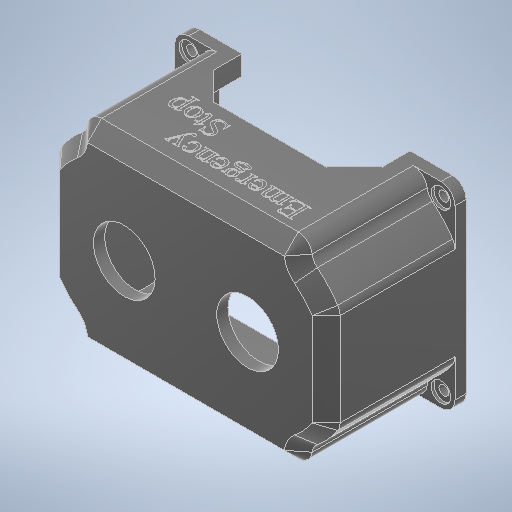
# Autodesk Inventor part: 3D_Estop-fix
Saved by Autodesk Inventor 2025.3 (Build 293356030, 356C)
## iProperties
Created: 2025-09-04
Part Number: 3D_Estop-fix
Material: 一般
Document SubType Name: Modeling
Designer: ibuki_ono
Density: 1 g/cm^3
Appearance: 滑らか - 黒
Author: ibuki_ono
## iProperties of the stored document 3D_Estop-fix_3D プリント.ipt
Created: 2025-09-05
Part Number: 3D_Estop-fix_3D プリント
Material: 一般
Document SubType Name: Modeling
Designer: ibuki_ono
Density: 1 g/cm^3
Appearance: 既定
Author: ibuki_ono
Autodesk Inventor part; units mm, degrees
ref_plane "YZ Plane" through (0, 0, 0) normal (1, 0, 0) x (0, 1, 0)
ref_plane "XZ Plane" through (0, 0, 0) normal (0, 1, 0) x (-1, 0, 0)
ref_plane "XY Plane" through (0, 0, 0) normal (0, 0, 1) x (1, 0, 0)
sketch "スケッチ1" plane through (0, 0, 0) normal (0, 0, 1) x (1, 0, 0)
  line L0 (-50, -35) -> (50, -35)
  line L1 (50, -35) -> (50, 35)
  line L2 (50, 35) -> (-50, 35)
  line L3 (-50, 35) -> (-50, -35)
  line L4 (-50, -35) -> (50, 35) construction
  line L5 (50, -35) -> (-50, 35) construction
  point P0 (0, 0)
  dimension "d0" = 100
  dimension "d1" = 70
  constraints: 12 end point, 2 midpoint, 2 parallel, 1 horizontal, 1 perpendicular
  measures "d0" distance of L2.end L1.end
  measures "d1" distance of L1.end L0.end
extrude "押し出し1" add sketch "スケッチ1" along normal blind 50
sketch "スケッチ2" plane through (0, 0, 50) normal (0, 0, 1) x (1, 0, 0)
  circle A0 centre (-22, 0) radius 11
  point P0 (0, 0)
  dimension "d4" = 22
  dimension "d5" = 22
  constraints: 1 centre point, 1 horizontal alignment
  measures "d4" diameter of A0
  measures "d5" distance of point (0, 0) A0.centre
extrude "押し出し2" cut sketch "スケッチ2" against normal through all
sketch "スケッチ3" plane through (0, 0, 0) normal (0, 0, -1) x (-1, 0, 0)
  line L0 (-38, 28) -> (38, 28)
  line L1 (38, 28) -> (38, -28)
  line L2 (38, -28) -> (-38, -28)
  line L3 (-38, -28) -> (-38, 28)
  line L4 (-38, 28) -> (38, -28) construction
  line L5 (38, 28) -> (-38, -28) construction
  circle A0 centre (22, 0) radius 11 projected
  point P0 (0, 0)
  dimension "d8" = 16
  dimension "d9" = 56
  constraints: 12 end point, 2 midpoint, 2 parallel, 1 horizontal, 1 perpendicular
  measures "d8" distance from line of L1 A0.centre
  measures "d9" distance of L0.end L1.end
extrude "押し出し3" cut sketch "スケッチ3" against normal blind 46
sketch "スケッチ4" plane through (0, 0, 50) normal (0, 0, 1) x (1, 0, 0)
  circle A0 centre (22, 0) radius 11
  point P0 (0, 0)
  dimension "d12" = 22
  dimension "d13" = 22
  constraints: 1 centre point, 1 horizontal alignment
  measures "d12" distance of point (0, 0) A0.centre
  measures "d13" diameter of A0
extrude "押し出し4" cut sketch "スケッチ4" against normal through all
sketch "スケッチ5" plane through (0, 0, 50) normal (0, 0, 1) x (1, 0, 0)
  circle A0 centre (-22, 0) radius 11 projected
  line L0 (50, -35) -> (50, 35) projected
  line L1 (50, 35) -> (-50, 35) projected
  line L2 (-50, 35) -> (-50, -35) projected
  line L3 (-50, -35) -> (50, -35) projected
  circle A1 centre (-20, 0) radius 35
  line L4 (-40, 35) -> (-40, -35)
  point P0 (0, 0)
  point P1 (-40, 28.7228)
  point P2 (-50, 18.0278)
  point P3 (-40, -28.7228)
  point P4 (-50, -18.0278)
  dimension "d16" = 70
  dimension "d17" = 10
  constraints: 2 end point, 2 point on line, 1 centre point, 1 perpendicular
  measures "d16" diameter of A1
  measures "d17" distance between parallel lines of L2 L4
extrude "押し出し5" cut sketch "スケッチ5" against normal blind 46 contours L3 L2 A1 L4 | L4 A1 L2 L1
sketch "スケッチ6" plane through (0, 0, 4) normal (0, 0, 1) x (1, 0, 0)
  line L0 (-50, 35) -> (-40, 35) projected
  line L1 (-40, -35) -> (-50, -35) projected
  line L2 (-45, 35) -> (-45, -35) construction
  point P0 (0, 0)
  point P1 (-45, 30)
  point P2 (-45, -30)
  dimension "d20" = 5
  dimension "d21" = 5
  constraints: 2 end point, 2 midpoint, 2 point on line
  measures "d20" distance from line of L0 point (-45, 30)
  measures "d21" distance from line of L1 point (-45, -30)
hole "穴1" at (-45, 30, 4) at (-45, -30, 4) direction (0, 0, -1) diameter 3.5 end through all counterbore diameter 7 counterbore depth 1
mirror "ミラー1" about plane through (0, 0, 0) normal (1, 0, 0) of "押し出し5", "穴1"
fillet "フィレット1" radius 5 16 edges at (-50, -35, 2) (-50, -18.0278, 27) (-40, -35, 27) (-40, -28.7228, 27) (40, -35, 27) (50, -35, 2) (40, -28.7228, 27) (50, -18.0278, 27) (50, 18.0278, 27) (40, 28.7228, 27) (40, 35, 27) (50, 35, 2) (-40, 35, 27) (-40, 28.7228, 27) (-50, 18.0278, 27) (-50, 35, 2)
chamfer "面取り1" distance 5 angle 45 20 edges at (0, 35, 50) (-38.3872, 33.7458, 50) (-40.6344, 28.7874, 50) (-45.8305, 23.6175, 50) (-49.7871, 18.0265, 50) (-50, 0, 50) (-49.7871, -18.0265, 50) (-45.8305, -23.6175, 50) (-40.6344, -28.7874, 50) (-38.3872, -33.7458, 50) (0, -35, 50) (38.3872, -33.7458, 50) (40.6344, -28.7874, 50) (45.8305, -23.6175, 50) (49.7871, -18.0265, 50) (50, 0, 50) (49.7871, 18.0265, 50) (45.8305, 23.6175, 50) (40.6344, 28.7874, 50) (38.3872, 33.7458, 50)
sketch "スケッチ7" plane through (-45, 35, 0) normal (0, 1, 0) x (1, 0, 0)
  line L0 (90, 0) -> (0, 0) projected
  line L1 (0, 0) -> (90, 0) projected
  line L2 (75, 0) -> (15, 0)
  line L3 (15, 0) -> (15, -20)
  line L4 (15, -20) -> (75, -20)
  line L5 (75, -20) -> (75, 0)
  point P0 (45, 0)
  point P1 (45, 0)
  point P2 (45, 0)
  point P3 (15, 0)
  dimension "d33" = 60
  dimension "d34" = 20
  constraints: 8 end point, 4 midpoint, 2 parallel, 1 horizontal, 1 perpendicular, 1 point on line
  measures "d33" distance of L4.end L3.end
  measures "d34" distance of L3.end L2.end
extrude "押し出し6" cut sketch "スケッチ7" against normal through all
chamfer "面取り2" distance 10 angle 45 4 edges at (30, 31.5, 20) (-30, 31.5, 20) (30, -31.5, 20) (-30, -31.5, 20)
sketch "スケッチ8" plane through (-45, 35, 4) normal (0, 1, 0) x (1, 0, 0)
  line L0 (75.4109, -38.3086) -> (10.7942, -38.3086) construction
  line L1 (10.7942, -38.3086) -> (10.7942, -18.6159) construction
  line L2 (10.7942, -18.6159) -> (75.4109, -18.6159) construction
  line L3 (75.4109, -18.6159) -> (75.4109, -38.3086) construction
  line L4 (73.2034, -37.9254) -> (73.2034, -35.1632)
  line L5 (73.2034, -35.1632) -> (71.665, -35.1632)
  spline S0 degree 2 poles (71.665, -35.1632) (71.0645, -35.1632) (70.8643, -35.3462) knots 0 0 0 1 1 1
  spline S1 degree 2 poles (70.8643, -35.3462) (70.5898, -35.5806) (70.5612, -36.1811) knots 0 0 0 1 1 1
  line L6 (70.5612, -36.1811) -> (70.3725, -36.1811)
  line L7 (70.3725, -36.1811) -> (70.3725, -33.7391)
  line L8 (70.3725, -33.7391) -> (70.5612, -33.7391)
  spline S2 degree 2 poles (70.5612, -33.7391) (70.6356, -34.2481) (70.7042, -34.3911) knots 0 0 0 1 1 1
  spline S3 degree 2 poles (70.7042, -34.3911) (70.8014, -34.5741) (71.2246, -34.78) (71.665, -34.78) knots 0 0 0 1 2 2 2
  line L9 (71.665, -34.78) -> (73.2034, -34.78)
  line L10 (73.2034, -34.78) -> (73.2034, -32.4752)
  spline S4 degree 2 poles (73.2034, -32.4752) (73.2034, -32.012) (73.1233, -31.8118) (72.9117, -31.6917) (72.6258, -31.6917) knots 0 0 0 1 2 3 3 3
  line L11 (72.6258, -31.6917) -> (71.4362, -31.6917)
  spline S5 degree 2 poles (71.4362, -31.6917) (70.8415, -31.6917) (70.3039, -31.8576) (70.058, -32.0978) knots 0 0 0 1 2 2 2
  spline S6 degree 2 poles (70.058, -32.0978) (69.7377, -32.4181) (69.4003, -33.0643) knots 0 0 0 1 1 1
  line L12 (69.4003, -33.0643) -> (69.1944, -33.0643)
  line L13 (69.1944, -33.0643) -> (69.8006, -31.3086)
  line L14 (69.8006, -31.3086) -> (75.1936, -31.3086)
  line L15 (75.1936, -31.3086) -> (75.1936, -31.4973)
  line L16 (75.1936, -31.4973) -> (74.9477, -31.4973)
  spline S7 degree 2 poles (74.9477, -31.4973) (74.696, -31.4973) (74.4787, -31.6174) knots 0 0 0 1 1 1
  spline S8 degree 2 poles (74.4787, -31.6174) (74.3129, -31.7032) (74.1928, -32.0349) (74.1928, -32.5496) knots 0 0 0 1 2 2 2
  line L17 (74.1928, -32.5496) -> (74.1928, -37.0904)
  spline S9 degree 2 poles (74.1928, -37.0904) (74.1928, -37.7596) (74.3243, -37.914) knots 0 0 0 1 1 1
  spline S10 degree 2 poles (74.3243, -37.914) (74.513, -38.1199) (74.9477, -38.1199) knots 0 0 0 1 1 1
  line L18 (74.9477, -38.1199) -> (75.1936, -38.1199)
  line L19 (75.1936, -38.1199) -> (75.1936, -38.3086)
  line L20 (75.1936, -38.3086) -> (69.7949, -38.3086)
  line L21 (69.7949, -38.3086) -> (69.7205, -36.7702)
  line L22 (69.7205, -36.7702) -> (69.9207, -36.7702)
  spline S11 degree 2 poles (69.9207, -36.7702) (70.0294, -37.3249) (70.2924, -37.7367) (70.5498, -37.8453) knots 0 0 0 1 2 2 2
  spline S12 degree 2 poles (70.5498, -37.8453) (70.7557, -37.9254) (71.2818, -37.9254) knots 0 0 0 1 1 1
  line L23 (71.2818, -37.9254) -> (73.2034, -37.9254)
  spline S13 degree 2 poles (67.2156, -35.1632) (66.7009, -35.6836) (66.6094, -35.7636) knots 0 0 0 1 1 1
  spline S14 degree 2 poles (66.6094, -35.7636) (66.3749, -35.9581) (65.8374, -36.1754) (65.5743, -36.1754) knots 0 0 0 1 2 2 2
  spline S15 degree 2 poles (65.5743, -36.1754) (65.1282, -36.1754) (64.4877, -35.655) (64.3848, -35.1632) knots 0 0 0 1 2 2 2
  spline S16 degree 2 poles (64.3848, -35.1632) (63.8529, -35.7865) (63.1209, -36.1754) (62.732, -36.1754) knots 0 0 0 1 2 2 2
  spline S17 degree 2 poles (62.732, -36.1754) (62.3545, -36.1754) (61.7769, -35.7865) (61.6053, -35.3519) knots 0 0 0 1 2 2 2
  spline S18 degree 2 poles (61.6053, -35.3519) (61.491, -35.0488) (61.491, -34.4083) knots 0 0 0 1 1 1
  line L24 (61.491, -34.4083) -> (61.491, -32.378)
  spline S19 degree 2 poles (61.491, -32.378) (61.491, -31.9377) (61.4223, -31.7718) knots 0 0 0 1 1 1
  spline S20 degree 2 poles (61.4223, -31.7718) (61.3709, -31.6574) (61.0906, -31.4973) (60.7761, -31.4973) knots 0 0 0 1 2 2 2
  line L25 (60.7761, -31.4973) -> (60.7761, -31.3086)
  line L26 (60.7761, -31.3086) -> (63.1151, -31.3086)
  line L27 (63.1151, -31.3086) -> (63.1151, -31.4973)
  line L28 (63.1151, -31.4973) -> (63.0179, -31.4973)
  spline S21 degree 2 poles (63.0179, -31.4973) (62.7091, -31.4973) (62.5375, -31.6174) knots 0 0 0 1 1 1
  spline S22 degree 2 poles (62.5375, -31.6174) (62.4232, -31.6975) (62.3717, -31.8805) knots 0 0 0 1 1 1
  spline S23 degree 2 poles (62.3717, -31.8805) (62.3488, -31.9663) (62.3488, -32.378) knots 0 0 0 1 1 1
  line L29 (62.3488, -32.378) -> (62.3488, -34.4083)
  spline S24 degree 2 poles (62.3488, -34.4083) (62.3488, -34.9859) (62.4861, -35.2203) knots 0 0 0 1 1 1
  spline S25 degree 2 poles (62.4861, -35.2203) (62.6862, -35.552) (63.1323, -35.552) knots 0 0 0 1 1 1
  spline S26 degree 2 poles (63.1323, -35.552) (63.4011, -35.552) (63.9558, -35.2775) (64.3447, -34.9058) knots 0 0 0 1 2 2 2
  line L30 (64.3447, -34.9058) -> (64.3562, -34.8486)
  line L31 (64.3562, -34.8486) -> (64.3447, -34.6313)
  line L32 (64.3447, -34.6313) -> (64.3447, -32.378)
  spline S27 degree 2 poles (64.3447, -32.378) (64.3447, -31.8919) (64.2361, -31.6574) (63.9387, -31.4973) (63.5784, -31.4973) knots 0 0 0 1 2 3 3 3
  line L33 (63.5784, -31.4973) -> (63.5784, -31.3086)
  line L34 (63.5784, -31.3086) -> (65.9689, -31.3086)
  line L35 (65.9689, -31.3086) -> (65.9689, -31.4973)
  spline S28 degree 2 poles (65.9689, -31.4973) (65.58, -31.4973) (65.2826, -31.6803) (65.2254, -31.869) knots 0 0 0 1 2 2 2
  spline S29 degree 2 poles (65.2254, -31.869) (65.2026, -31.9548) (65.2026, -32.378) knots 0 0 0 1 1 1
  line L36 (65.2026, -32.378) -> (65.2026, -34.4083)
  spline S30 degree 2 poles (65.2026, -34.4083) (65.2026, -34.9859) (65.3741, -35.2375) knots 0 0 0 1 1 1
  spline S31 degree 2 poles (65.3741, -35.2375) (65.5972, -35.5692) (66.0032, -35.5692) knots 0 0 0 1 1 1
  spline S32 degree 2 poles (66.0032, -35.5692) (66.2834, -35.5692) (66.558, -35.4205) knots 0 0 0 1 1 1
  spline S33 degree 2 poles (66.558, -35.4205) (66.9812, -35.1917) (67.2156, -34.9058) knots 0 0 0 1 1 1
  line L37 (67.2156, -34.9058) -> (67.2156, -32.378)
  spline S34 degree 2 poles (67.2156, -32.378) (67.2156, -31.9148) (67.0898, -31.6346) (66.8325, -31.4973) (66.4493, -31.4973) knots 0 0 0 1 2 3 3 3
  line L38 (66.4493, -31.4973) -> (66.4493, -31.3086)
  line L39 (66.4493, -31.3086) -> (68.7941, -31.3086)
  line L40 (68.7941, -31.3086) -> (68.7941, -31.4973)
  spline S35 degree 2 poles (68.7941, -31.4973) (68.4681, -31.4973) (68.2107, -31.6346) (68.0735, -31.9377) (68.0735, -32.378) knots 0 0 0 1 2 3 3 3
  line L41 (68.0735, -32.378) -> (68.0735, -34.1852)
  spline S36 degree 2 poles (68.0735, -34.1852) (68.0735, -34.963) (68.1192, -35.186) knots 0 0 0 1 1 1
  spline S37 degree 2 poles (68.1192, -35.186) (68.1535, -35.3576) (68.3137, -35.4891) (68.4452, -35.4891) knots 0 0 0 1 2 2 2
  spline S38 degree 2 poles (68.4452, -35.4891) (68.5882, -35.4891) (68.7883, -35.4091) knots 0 0 0 1 1 1
  line L42 (68.7883, -35.4091) -> (68.8684, -35.5978)
  line L43 (68.8684, -35.5978) -> (67.4387, -36.1754)
  line L44 (67.4387, -36.1754) -> (67.2156, -36.1754)
  line L45 (67.2156, -36.1754) -> (67.2156, -35.1632)
  spline S39 degree 2 poles (59.6037, -34.2538) (59.6094, -33.2016) (59.0947, -32.6068) knots 0 0 0 1 1 1
  spline S40 degree 2 poles (59.0947, -32.6068) (58.5743, -32.0063) (57.8766, -32.0063) knots 0 0 0 1 1 1
  spline S41 degree 2 poles (57.8766, -32.0063) (57.4133, -32.0063) (56.7271, -32.5153) (56.4926, -33.1386) knots 0 0 0 1 2 2 2
  line L46 (56.4926, -33.1386) -> (56.3325, -33.0357)
  spline S42 degree 2 poles (56.3325, -33.0357) (56.4411, -32.3266) (57.482, -31.1656) (58.2712, -31.1656) knots 0 0 0 1 2 2 2
  spline S43 degree 2 poles (58.2712, -31.1656) (59.1233, -31.1656) (60.3357, -32.4924) (60.3357, -33.6076) knots 0 0 0 1 2 2 2
  spline S44 degree 2 poles (60.3357, -33.6076) (60.3357, -34.82) (59.089, -36.1754) (58.1511, -36.1754) knots 0 0 0 1 2 2 2
  spline S45 degree 2 poles (58.1511, -36.1754) (57.3562, -36.1754) (56.3325, -35.1288) (56.3325, -34.2538) knots 0 0 0 1 2 2 2
  line L47 (56.3325, -34.2538) -> (59.6037, -34.2538)
  line L48 (59.6037, -34.5512) -> (57.4076, -34.5512)
  spline S46 degree 2 poles (57.4076, -34.5512) (57.4362, -35.003) (57.5163, -35.1917) knots 0 0 0 1 1 1
  spline S47 degree 2 poles (57.5163, -35.1917) (57.6478, -35.4777) (58.1568, -35.8094) (58.437, -35.8094) knots 0 0 0 1 2 2 2
  spline S48 degree 2 poles (58.437, -35.8094) (58.866, -35.8094) (59.5465, -35.146) (59.6037, -34.5512) knots 0 0 0 1 2 2 2
  line L49 (54.3137, -36.1754) -> (54.3137, -35.1117)
  spline S49 degree 2 poles (54.3137, -35.1117) (53.7189, -36.1754) (53.0955, -36.1754) knots 0 0 0 1 1 1
  spline S50 degree 2 poles (53.0955, -36.1754) (52.8153, -36.1754) (52.4436, -35.8323) (52.4436, -35.6035) knots 0 0 0 1 2 2 2
  spline S51 degree 2 poles (52.4436, -35.6035) (52.4436, -35.4034) (52.7124, -35.1231) (52.8954, -35.1231) knots 0 0 0 1 2 2 2
  spline S52 degree 2 poles (52.8954, -35.1231) (53.0784, -35.1231) (53.5245, -35.4777) (53.6331, -35.4777) knots 0 0 0 1 2 2 2
  spline S53 degree 2 poles (53.6331, -35.4777) (53.7246, -35.4777) (53.8333, -35.3748) knots 0 0 0 1 1 1
  spline S54 degree 2 poles (53.8333, -35.3748) (54.0678, -35.1632) (54.3137, -34.677) knots 0 0 0 1 1 1
  line L50 (54.3137, -34.677) -> (54.3137, -32.4123)
  spline S55 degree 2 poles (54.3137, -32.4123) (54.3137, -32.0177) (54.2165, -31.8176) knots 0 0 0 1 1 1
  spline S56 degree 2 poles (54.2165, -31.8176) (54.1478, -31.6803) (53.8104, -31.4973) (53.4901, -31.4973) knots 0 0 0 1 2 2 2
  line L51 (53.4901, -31.4973) -> (53.4901, -31.3086)
  line L52 (53.4901, -31.3086) -> (55.915, -31.3086)
  line L53 (55.915, -31.3086) -> (55.915, -31.4973)
  spline S57 degree 2 poles (55.915, -31.4973) (55.5547, -31.4973) (55.3774, -31.6117) knots 0 0 0 1 1 1
  spline S58 degree 2 poles (55.3774, -31.6117) (55.2516, -31.6917) (55.2001, -31.8748) knots 0 0 0 1 1 1
  spline S59 degree 2 poles (55.2001, -31.8748) (55.1715, -31.9663) (55.1715, -32.378) knots 0 0 0 1 1 1
  line L54 (55.1715, -32.378) -> (55.1715, -34.2024)
  spline S60 degree 2 poles (55.1715, -34.2024) (55.1715, -35.0259) (55.2401, -35.3404) (55.4174, -35.4891) (55.5547, -35.4891) knots 0 0 0 1 2 3 3 3
  spline S61 degree 2 poles (55.5547, -35.4891) (55.7148, -35.4891) (55.915, -35.4091) knots 0 0 0 1 1 1
  line L55 (55.915, -35.4091) -> (55.9665, -35.5978)
  line L56 (55.9665, -35.5978) -> (54.531, -36.1754)
  line L57 (54.531, -36.1754) -> (54.3137, -36.1754)
  spline S62 degree 2 poles (50.9166, -33.0357) (51.3513, -33.2473) (51.8145, -34.0022) (51.8145, -34.4654) knots 0 0 0 1 2 2 2
  spline S63 degree 2 poles (51.8145, -34.4654) (51.8145, -35.1632) (50.7565, -36.1754) (49.9272, -36.1754) knots 0 0 0 1 2 2 2
  spline S64 degree 2 poles (49.9272, -36.1754) (49.2524, -36.1754) (48.7548, -35.8437) knots 0 0 0 1 1 1
  line L58 (48.7548, -35.8437) -> (47.754, -35.8437)
  spline S65 degree 2 poles (47.754, -35.8437) (47.531, -35.8437) (47.4566, -35.8208) (47.4395, -35.7865) knots 0 0 0 1 2 2 2
  spline S66 degree 2 poles (47.4395, -35.7865) (47.4109, -35.7408) (47.4109, -35.6207) knots 0 0 0 1 1 1
  spline S67 degree 2 poles (47.4109, -35.6207) (47.4109, -35.4891) (47.4395, -35.4377) knots 0 0 0 1 1 1
  spline S68 degree 2 poles (47.4395, -35.4377) (47.4509, -35.4091) (47.531, -35.3805) (47.754, -35.3805) knots 0 0 0 1 2 2 2
  line L59 (47.754, -35.3805) -> (48.3717, -35.3805)
  spline S69 degree 2 poles (48.3717, -35.3805) (48.08, -35.0087) (48.08, -34.4311) knots 0 0 0 1 1 1
  spline S70 degree 2 poles (48.08, -34.4311) (48.08, -33.7677) (49.0923, -32.8298) (49.9444, -32.8298) knots 0 0 0 1 2 2 2
  spline S71 degree 2 poles (49.9444, -32.8298) (50.2932, -32.8298) (50.665, -32.9328) knots 0 0 0 1 1 1
  spline S72 degree 2 poles (50.665, -32.9328) (50.888, -32.7383) (51.0482, -32.4467) (51.0482, -32.3437) knots 0 0 0 1 2 2 2
  spline S73 degree 2 poles (51.0482, -32.3437) (51.0482, -32.2522) (50.8766, -32.0864) (50.6307, -32.052) knots 0 0 0 1 2 2 2
  spline S74 degree 2 poles (50.6307, -32.052) (50.4877, -32.0292) (49.9044, -32.0177) knots 0 0 0 1 1 1
  spline S75 degree 2 poles (49.9044, -32.0177) (48.8406, -31.9891) (48.5261, -31.9434) knots 0 0 0 1 1 1
  spline S76 degree 2 poles (48.5261, -31.9434) (48.0457, -31.8748) (47.4738, -31.2971) (47.4738, -30.8797) knots 0 0 0 1 2 2 2
  spline S77 degree 2 poles (47.4738, -30.8797) (47.4738, -30.2963) (48.0228, -29.7873) knots 0 0 0 1 1 1
  spline S78 degree 2 poles (48.0228, -29.7873) (48.8292, -29.0324) (50.1274, -29.0324) knots 0 0 0 1 1 1
  spline S79 degree 2 poles (50.1274, -29.0324) (51.1225, -29.0324) (51.8088, -29.4785) knots 0 0 0 1 1 1
  spline S80 degree 2 poles (51.8088, -29.4785) (52.1977, -29.7359) (52.1977, -30.0161) knots 0 0 0 1 1 1
  spline S81 degree 2 poles (52.1977, -30.0161) (52.1977, -30.1419) (52.1405, -30.262) knots 0 0 0 1 1 1
  spline S82 degree 2 poles (52.1405, -30.262) (52.0547, -30.4565) (51.7802, -30.7939) knots 0 0 0 1 1 1
  spline S83 degree 2 poles (51.7802, -30.7939) (51.7401, -30.8396) (51.254, -31.3486) knots 0 0 0 1 1 1
  spline S84 degree 2 poles (51.254, -31.3486) (51.5171, -31.5087) (51.7401, -31.7661) (51.7401, -31.9262) knots 0 0 0 1 2 2 2
  spline S85 degree 2 poles (51.7401, -31.9262) (51.7401, -32.1035) (51.4485, -32.5896) (50.9166, -33.0357) knots 0 0 0 1 2 2 2
  spline S86 degree 2 poles (50.9681, -31.3086) (51.214, -31.0455) (51.4599, -30.5937) (51.4599, -30.405) knots 0 0 0 1 2 2 2
  spline S87 degree 2 poles (51.4599, -30.405) (51.4599, -30.1591) (51.1625, -29.9761) knots 0 0 0 1 1 1
  spline S88 degree 2 poles (51.1625, -29.9761) (50.6421, -29.6558) (49.6642, -29.6558) knots 0 0 0 1 1 1
  spline S89 degree 2 poles (49.6642, -29.6558) (48.7377, -29.6558) (47.8513, -30.3078) (47.8513, -30.6738) knots 0 0 0 1 2 2 2
  spline S90 degree 2 poles (47.8513, -30.6738) (47.8513, -30.9426) (48.1143, -31.0569) knots 0 0 0 1 1 1
  spline S91 degree 2 poles (48.1143, -31.0569) (48.3831, -31.1656) (49.1781, -31.1885) knots 0 0 0 1 1 1
  spline S92 degree 2 poles (49.1781, -31.1885) (50.3447, -31.2171) (50.9681, -31.3086) knots 0 0 0 1 1 1
  spline S93 degree 2 poles (50.0187, -35.9295) (50.4019, -35.9295) (50.9166, -35.3233) (50.9166, -34.6942) knots 0 0 0 1 2 2 2
  spline S94 degree 2 poles (50.9166, -34.6942) (50.9166, -33.8764) (50.5678, -33.4303) knots 0 0 0 1 1 1
  spline S95 degree 2 poles (50.5678, -33.4303) (50.299, -33.0872) (49.8815, -33.0872) knots 0 0 0 1 1 1
  spline S96 degree 2 poles (49.8815, -33.0872) (49.4926, -33.0872) (48.9836, -33.6762) (48.9836, -34.3053) knots 0 0 0 1 2 2 2
  spline S97 degree 2 poles (48.9836, -34.3053) (48.9836, -35.1231) (49.3382, -35.5864) knots 0 0 0 1 1 1
  spline S98 degree 2 poles (49.3382, -35.5864) (49.6013, -35.9295) (50.0187, -35.9295) knots 0 0 0 1 1 1
  spline S99 degree 2 poles (46.0955, -34.2538) (46.1013, -33.2016) (45.5865, -32.6068) knots 0 0 0 1 1 1
  spline S100 degree 2 poles (45.5865, -32.6068) (45.0661, -32.0063) (44.3684, -32.0063) knots 0 0 0 1 1 1
  spline S101 degree 2 poles (44.3684, -32.0063) (43.9052, -32.0063) (43.2189, -32.5153) (42.9844, -33.1386) knots 0 0 0 1 2 2 2
  line L60 (42.9844, -33.1386) -> (42.8243, -33.0357)
  spline S102 degree 2 poles (42.8243, -33.0357) (42.933, -32.3266) (43.9738, -31.1656) (44.763, -31.1656) knots 0 0 0 1 2 2 2
  spline S103 degree 2 poles (44.763, -31.1656) (45.6151, -31.1656) (46.8276, -32.4924) (46.8276, -33.6076) knots 0 0 0 1 2 2 2
  spline S104 degree 2 poles (46.8276, -33.6076) (46.8276, -34.82) (45.5808, -36.1754) (44.6429, -36.1754) knots 0 0 0 1 2 2 2
  spline S105 degree 2 poles (44.6429, -36.1754) (43.848, -36.1754) (42.8243, -35.1288) (42.8243, -34.2538) knots 0 0 0 1 2 2 2
  line L61 (42.8243, -34.2538) -> (46.0955, -34.2538)
  line L62 (46.0955, -34.5512) -> (43.8995, -34.5512)
  spline S106 degree 2 poles (43.8995, -34.5512) (43.9281, -35.003) (44.0081, -35.1917) knots 0 0 0 1 1 1
  spline S107 degree 2 poles (44.0081, -35.1917) (44.1397, -35.4777) (44.6486, -35.8094) (44.9289, -35.8094) knots 0 0 0 1 2 2 2
  spline S108 degree 2 poles (44.9289, -35.8094) (45.3578, -35.8094) (46.0383, -35.146) (46.0955, -34.5512) knots 0 0 0 1 2 2 2
  spline S109 degree 2 poles (40.8112, -35.1746) (39.982, -36.1754) (39.2271, -36.1754) knots 0 0 0 1 1 1
  spline S110 degree 2 poles (39.2271, -36.1754) (38.8439, -36.1754) (38.2892, -35.7865) (38.1233, -35.3462) knots 0 0 0 1 2 2 2
  spline S111 degree 2 poles (38.1233, -35.3462) (38.0089, -35.0373) (38.0089, -34.3968) knots 0 0 0 1 1 1
  line L63 (38.0089, -34.3968) -> (38.0089, -32.378)
  spline S112 degree 2 poles (38.0089, -32.378) (38.0089, -31.9319) (37.9346, -31.7718) knots 0 0 0 1 1 1
  spline S113 degree 2 poles (37.9346, -31.7718) (37.8774, -31.6403) (37.6258, -31.4973) (37.2883, -31.4973) knots 0 0 0 1 2 2 2
  line L64 (37.2883, -31.4973) -> (37.2883, -31.3086)
  line L65 (37.2883, -31.3086) -> (39.6331, -31.3086)
  line L66 (39.6331, -31.3086) -> (39.6331, -31.4973)
  line L67 (39.6331, -31.4973) -> (39.5359, -31.4973)
  spline S114 degree 2 poles (39.5359, -31.4973) (39.2042, -31.4973) (38.9411, -31.6975) (38.8897, -31.8919) knots 0 0 0 1 2 2 2
  spline S115 degree 2 poles (38.8897, -31.8919) (38.8668, -31.972) (38.8668, -32.378) knots 0 0 0 1 1 1
  line L68 (38.8668, -32.378) -> (38.8668, -34.311)
  spline S116 degree 2 poles (38.8668, -34.311) (38.8668, -34.9573) (39.1985, -35.5406) (39.5931, -35.5406) knots 0 0 0 1 2 2 2
  spline S117 degree 2 poles (39.5931, -35.5406) (40.205, -35.5406) (40.8112, -34.8715) knots 0 0 0 1 1 1
  line L69 (40.8112, -34.8715) -> (40.8112, -32.378)
  spline S118 degree 2 poles (40.8112, -32.378) (40.8112, -31.8976) (40.754, -31.7833) knots 0 0 0 1 1 1
  spline S119 degree 2 poles (40.754, -31.7833) (40.6797, -31.6346) (40.4281, -31.4973) (40.0392, -31.4973) knots 0 0 0 1 2 2 2
  line L70 (40.0392, -31.4973) -> (40.0392, -31.3086)
  line L71 (40.0392, -31.3086) -> (42.3897, -31.3086)
  line L72 (42.3897, -31.3086) -> (42.3897, -31.4973)
  line L73 (42.3897, -31.4973) -> (42.2867, -31.4973)
  spline S120 degree 2 poles (42.2867, -31.4973) (41.9207, -31.4973) (41.6691, -31.8633) (41.6691, -32.378) knots 0 0 0 1 2 2 2
  line L74 (41.6691, -32.378) -> (41.6691, -34.1337)
  spline S121 degree 2 poles (41.6691, -34.1337) (41.6691, -34.9801) (41.7491, -35.3519) (41.9093, -35.4891) (42.0408, -35.4891) knots 0 0 0 1 2 3 3 3
  spline S122 degree 2 poles (42.0408, -35.4891) (42.1838, -35.4891) (42.3839, -35.4091) knots 0 0 0 1 1 1
  line L75 (42.3839, -35.4091) -> (42.464, -35.5978)
  line L76 (42.464, -35.5978) -> (41.0343, -36.1754)
  line L77 (41.0343, -36.1754) -> (40.8112, -36.1754)
  line L78 (40.8112, -36.1754) -> (40.8112, -35.1746)
  spline S123 degree 2 poles (32.8848, -33.1043) (33.0735, -32.1721) (34.1887, -31.1656) (34.8692, -31.1656) knots 0 0 0 1 2 2 2
  spline S124 degree 2 poles (34.8692, -31.1656) (35.6756, -31.1656) (36.8709, -32.5153) (36.8709, -33.6705) knots 0 0 0 1 2 2 2
  spline S125 degree 2 poles (36.8709, -33.6705) (36.8709, -34.78) (35.5441, -36.1754) (34.6119, -36.1754) knots 0 0 0 1 2 2 2
  spline S126 degree 2 poles (34.6119, -36.1754) (33.9142, -36.1754) (33.0163, -35.4377) (33.0163, -35.0431) knots 0 0 0 1 2 2 2
  spline S127 degree 2 poles (33.0163, -35.0431) (33.0163, -34.8429) (33.2679, -34.6027) (33.4967, -34.6027) knots 0 0 0 1 2 2 2
  spline S128 degree 2 poles (33.4967, -34.6027) (33.7998, -34.6027) (33.9542, -34.7971) knots 0 0 0 1 1 1
  spline S129 degree 2 poles (33.9542, -34.7971) (34.0457, -34.9058) (34.1029, -35.512) (34.2802, -35.6721) knots 0 0 0 1 2 2 2
  spline S130 degree 2 poles (34.2802, -35.6721) (34.4632, -35.8266) (34.7834, -35.8266) knots 0 0 0 1 1 1
  spline S131 degree 2 poles (34.7834, -35.8266) (35.3039, -35.8266) (35.6184, -35.4434) knots 0 0 0 1 1 1
  spline S132 degree 2 poles (35.6184, -35.4434) (36.0359, -34.9401) (36.0359, -34.1109) knots 0 0 0 1 1 1
  spline S133 degree 2 poles (36.0359, -34.1109) (36.0359, -33.2645) (35.2066, -31.972) (34.4975, -31.972) knots 0 0 0 1 2 2 2
  spline S134 degree 2 poles (34.4975, -31.972) (33.9885, -31.972) (33.5882, -32.3151) knots 0 0 0 1 1 1
  spline S135 degree 2 poles (33.5882, -32.3151) (33.3022, -32.5496) (33.0334, -33.1787) knots 0 0 0 1 1 1
  line L79 (33.0334, -33.1787) -> (32.8848, -33.1043)
  line L80 (32.4844, -36.0382) -> (30.2769, -36.0382)
  line L81 (30.2769, -36.0382) -> (30.2769, -35.8494)
  line L82 (30.2769, -35.8494) -> (30.3856, -35.8494)
  spline S136 degree 2 poles (30.3856, -35.8494) (30.6143, -35.8494) (30.8488, -35.6493) (30.8488, -35.5006) knots 0 0 0 1 2 2 2
  spline S137 degree 2 poles (30.8488, -35.5006) (30.8488, -35.2947) (30.6772, -34.9401) knots 0 0 0 1 1 1
  line L83 (30.6772, -34.9401) -> (29.522, -32.5496)
  line L84 (29.522, -32.5496) -> (28.4697, -35.1689)
  spline S138 degree 2 poles (28.4697, -35.1689) (28.3839, -35.3805) (28.3839, -35.5864) knots 0 0 0 1 1 1
  spline S139 degree 2 poles (28.3839, -35.5864) (28.3839, -35.6779) (28.4182, -35.7236) knots 0 0 0 1 1 1
  spline S140 degree 2 poles (28.4182, -35.7236) (28.4583, -35.7808) (28.6356, -35.8494) (28.8586, -35.8494) knots 0 0 0 1 2 2 2
  line L85 (28.8586, -35.8494) -> (28.8586, -36.0382)
  line L86 (28.8586, -36.0382) -> (27.3202, -36.0382)
  line L87 (27.3202, -36.0382) -> (27.3202, -35.8494)
  spline S141 degree 2 poles (27.3202, -35.8494) (27.5147, -35.8266) (27.7205, -35.7065) (27.8406, -35.5349) knots 0 0 0 1 2 2 2
  spline S142 degree 2 poles (27.8406, -35.5349) (27.8864, -35.4605) (28.0179, -35.1346) knots 0 0 0 1 1 1
  line L88 (28.0179, -35.1346) -> (29.9395, -30.4221)
  spline S143 degree 2 poles (29.9395, -30.4221) (30.2197, -29.7359) (31.1233, -29.0324) (31.5408, -29.0324) knots 0 0 0 1 2 2 2
  spline S144 degree 2 poles (31.5408, -29.0324) (31.8439, -29.0324) (32.2385, -29.3813) (32.2385, -29.61) knots 0 0 0 1 2 2 2
  spline S145 degree 2 poles (32.2385, -29.61) (32.2385, -29.8274) (31.9526, -30.0904) (31.7066, -30.0904) knots 0 0 0 1 2 2 2
  spline S146 degree 2 poles (31.7066, -30.0904) (31.5351, -30.0904) (31.2434, -29.9761) knots 0 0 0 1 1 1
  spline S147 degree 2 poles (31.2434, -29.9761) (31.0318, -29.9017) (30.9803, -29.9017) knots 0 0 0 1 1 1
  spline S148 degree 2 poles (30.9803, -29.9017) (30.8259, -29.9017) (30.4599, -30.222) (30.2769, -30.6795) knots 0 0 0 1 2 2 2
  line L89 (30.2769, -30.6795) -> (29.9452, -31.503)
  line L90 (29.9452, -31.503) -> (31.638, -35.0602)
  spline S149 degree 2 poles (31.638, -35.0602) (31.7181, -35.2203) (31.8897, -35.4605) knots 0 0 0 1 1 1
  spline S150 degree 2 poles (31.8897, -35.4605) (32.0155, -35.6435) (32.1013, -35.7065) knots 0 0 0 1 1 1
  spline S151 degree 2 poles (32.1013, -35.7065) (32.2214, -35.7865) (32.4844, -35.8494) knots 0 0 0 1 1 1
  line L91 (32.4844, -35.8494) -> (32.4844, -36.0382)
  line L92 (30.9174, -27.3972) -> (30.9174, -24.9781)
  line L93 (30.9174, -24.9781) -> (31.1062, -24.9781)
  spline S152 degree 2 poles (31.1062, -24.9781) (31.1977, -25.6758) (31.6838, -26.4993) (32.5702, -26.9854) (33.0506, -26.9854) knots 0 0 0 1 2 3 3 3
  spline S153 degree 2 poles (33.0506, -26.9854) (33.5882, -26.9854) (34.2916, -26.3278) (34.2916, -25.9103) knots 0 0 0 1 2 2 2
  spline S154 degree 2 poles (34.2916, -25.9103) (34.2916, -25.59) (34.0686, -25.327) knots 0 0 0 1 1 1
  spline S155 degree 2 poles (34.0686, -25.327) (33.7483, -24.9381) (32.5416, -24.2918) knots 0 0 0 1 1 1
  spline S156 degree 2 poles (32.5416, -24.2918) (31.5637, -23.7657) (30.8431, -23.2052) (30.4542, -22.4389) (30.4542, -22.0214) knots 0 0 0 1 2 3 3 3
  spline S157 degree 2 poles (30.4542, -22.0214) (30.4542, -21.2265) (31.6895, -20.077) (32.6617, -20.077) knots 0 0 0 1 2 2 2
  spline S158 degree 2 poles (32.6617, -20.077) (32.9648, -20.077) (33.2336, -20.1227) knots 0 0 0 1 1 1
  spline S159 degree 2 poles (33.2336, -20.1227) (33.3937, -20.1513) (34.4003, -20.4773) (34.5375, -20.4773) knots 0 0 0 1 2 2 2
  spline S160 degree 2 poles (34.5375, -20.4773) (34.6633, -20.4773) (34.8178, -20.3229) (34.8521, -20.077) knots 0 0 0 1 2 2 2
  line L94 (34.8521, -20.077) -> (35.0408, -20.077)
  line L95 (35.0408, -20.077) -> (35.0408, -22.4789)
  line L96 (35.0408, -22.4789) -> (34.8521, -22.4789)
  spline S161 degree 2 poles (34.8521, -22.4789) (34.7205, -21.724) (34.263, -20.9748) (33.3251, -20.4773) (32.7704, -20.4773) knots 0 0 0 1 2 3 3 3
  spline S162 degree 2 poles (32.7704, -20.4773) (32.1241, -20.4773) (31.3749, -21.1578) (31.3749, -21.6268) knots 0 0 0 1 2 2 2
  spline S163 degree 2 poles (31.3749, -21.6268) (31.3749, -21.8841) (31.6609, -22.4103) (31.9583, -22.639) knots 0 0 0 1 2 2 2
  spline S164 degree 2 poles (31.9583, -22.639) (32.1584, -22.7935) (33.9599, -23.8) (34.7205, -24.4005) (35.1151, -25.1211) (35.1151, -25.5557) knots 0 0 0 1 2 3 4 4 4
  spline S165 degree 2 poles (35.1151, -25.5557) (35.1151, -26.3106) (33.9542, -27.3972) (33.0563, -27.3972) knots 0 0 0 1 2 2 2
  spline S166 degree 2 poles (33.0563, -27.3972) (32.5016, -27.3972) (31.8725, -27.1227) knots 0 0 0 1 1 1
  spline S167 degree 2 poles (31.8725, -27.1227) (31.5808, -26.9969) (31.4607, -26.9969) knots 0 0 0 1 1 1
  spline S168 degree 2 poles (31.4607, -26.9969) (31.3292, -26.9969) (31.1576, -27.157) (31.1062, -27.3972) knots 0 0 0 1 2 2 2
  line L97 (31.1062, -27.3972) -> (30.9174, -27.3972)
  line L98 (28.1895, -26.5222) -> (28.1895, -24.9667)
  line L99 (28.1895, -24.9667) -> (27.0857, -24.9667)
  line L100 (27.0857, -24.9667) -> (27.0857, -24.6064)
  line L101 (27.0857, -24.6064) -> (28.1895, -24.6064)
  line L102 (28.1895, -24.6064) -> (28.1895, -21.5353)
  spline S169 degree 2 poles (28.1895, -21.5353) (28.1895, -21.0778) (27.9264, -20.7575) (27.7205, -20.7575) knots 0 0 0 1 2 2 2
  spline S170 degree 2 poles (27.7205, -20.7575) (27.549, -20.7575) (27.223, -20.9691) (27.1372, -21.175) knots 0 0 0 1 2 2 2
  line L103 (27.1372, -21.175) -> (26.937, -21.175)
  spline S171 degree 2 poles (26.937, -21.175) (27.12, -20.666) (27.7834, -20.157) (28.1323, -20.157) knots 0 0 0 1 2 2 2
  spline S172 degree 2 poles (28.1323, -20.157) (28.3725, -20.157) (28.83, -20.4201) (29.0473, -20.9119) (29.0473, -21.4209) knots 0 0 0 1 2 3 3 3
  line L104 (29.0473, -21.4209) -> (29.0473, -24.6064)
  line L105 (29.0473, -24.6064) -> (29.7965, -24.6064)
  line L106 (29.7965, -24.6064) -> (29.7965, -24.7779)
  spline S173 degree 2 poles (29.7965, -24.7779) (29.5106, -24.8923) (28.9158, -25.4299) (28.6813, -25.8016) knots 0 0 0 1 2 2 2
  spline S174 degree 2 poles (28.6813, -25.8016) (28.5612, -26.0018) (28.3496, -26.5222) knots 0 0 0 1 1 1
  line L107 (28.3496, -26.5222) -> (28.1895, -26.5222)
  spline S175 degree 2 poles (24.3178, -25.1039) (23.2426, -25.1039) (22.5964, -24.2861) knots 0 0 0 1 1 1
  spline S176 degree 2 poles (22.5964, -24.2861) (22.0416, -23.5941) (22.0416, -22.6905) knots 0 0 0 1 1 1
  spline S177 degree 2 poles (22.0416, -22.6905) (22.0416, -22.0557) (22.6535, -20.7518) (23.7173, -20.0941) (24.3749, -20.0941) knots 0 0 0 1 2 3 3 3
  spline S178 degree 2 poles (24.3749, -20.0941) (25.4444, -20.0941) (26.0735, -20.9462) knots 0 0 0 1 1 1
  spline S179 degree 2 poles (26.0735, -20.9462) (26.6053, -21.6611) (26.6053, -22.5533) knots 0 0 0 1 1 1
  spline S180 degree 2 poles (26.6053, -22.5533) (26.6053, -23.2052) (25.9591, -24.492) (24.9068, -25.1039) (24.3178, -25.1039) knots 0 0 0 1 2 3 3 3
  spline S181 degree 2 poles (24.4779, -24.7665) (24.7524, -24.7665) (25.3014, -24.4405) (25.6446, -23.6284) (25.6446, -22.9879) knots 0 0 0 1 2 3 3 3
  spline S182 degree 2 poles (25.6446, -22.9879) (25.6446, -21.9585) (24.8267, -20.4601) (24.1519, -20.4601) knots 0 0 0 1 2 2 2
  spline S183 degree 2 poles (24.1519, -20.4601) (23.6544, -20.4601) (23.0024, -21.2837) (23.0024, -22.2902) knots 0 0 0 1 2 2 2
  spline S184 degree 2 poles (23.0024, -22.2902) (23.0024, -23.5484) (23.5457, -24.2689) knots 0 0 0 1 1 1
  spline S185 degree 2 poles (23.5457, -24.2689) (23.9117, -24.7665) (24.4779, -24.7665) knots 0 0 0 1 1 1
  line L108 (21.6813, -24.4977) -> (20.223, -25.0868)
  line L109 (20.223, -25.0868) -> (20.0285, -25.0868)
  line L110 (20.0285, -25.0868) -> (20.0285, -23.9773)
  spline S186 degree 2 poles (20.0285, -23.9773) (19.6625, -24.6006) (18.9248, -25.1039) (18.5187, -25.1039) knots 0 0 0 1 2 2 2
  spline S187 degree 2 poles (18.5187, -25.1039) (17.8039, -25.1039) (17.3292, -24.5492) knots 0 0 0 1 1 1
  spline S188 degree 2 poles (17.3292, -24.5492) (16.7459, -23.8629) (16.7459, -22.7706) knots 0 0 0 1 1 1
  spline S189 degree 2 poles (16.7459, -22.7706) (16.7459, -21.5467) (17.4493, -20.7518) knots 0 0 0 1 1 1
  spline S190 degree 2 poles (17.4493, -20.7518) (18.0269, -20.0941) (18.9019, -20.0941) knots 0 0 0 1 1 1
  spline S191 degree 2 poles (18.9019, -20.0941) (19.2851, -20.0941) (19.5653, -20.2028) knots 0 0 0 1 1 1
  spline S192 degree 2 poles (19.5653, -20.2028) (19.7712, -20.2771) (20.0285, -20.5116) knots 0 0 0 1 1 1
  line L111 (20.0285, -20.5116) -> (20.0285, -19.0704)
  spline S193 degree 2 poles (20.0285, -19.0704) (20.0285, -18.5843) (19.9084, -18.3212) (19.6168, -18.1668) (19.2279, -18.1668) knots 0 0 0 1 2 3 3 3
  line L112 (19.2279, -18.1668) -> (19.2279, -17.9781)
  line L113 (19.2279, -17.9781) -> (21.7099, -17.9781)
  line L114 (21.7099, -17.9781) -> (21.7099, -18.1668)
  line L115 (21.7099, -18.1668) -> (21.5784, -18.1668)
  spline S194 degree 2 poles (21.5784, -18.1668) (21.2982, -18.1611) (21.0923, -18.2755) knots 0 0 0 1 1 1
  spline S195 degree 2 poles (21.0923, -18.2755) (20.995, -18.3327) (20.8864, -18.5843) (20.8864, -19.1047) knots 0 0 0 1 2 2 2
  line L116 (20.8864, -19.1047) -> (20.8864, -23.5712)
  spline S196 degree 2 poles (20.8864, -23.5712) (20.8864, -24.0345) (20.9665, -24.2804) (21.1495, -24.4062) (21.3039, -24.4062) knots 0 0 0 1 2 3 3 3
  spline S197 degree 2 poles (21.3039, -24.4062) (21.4297, -24.4062) (21.6184, -24.3319) knots 0 0 0 1 1 1
  line L117 (21.6184, -24.3319) -> (21.6813, -24.4977)
  line L118 (20.0285, -23.6742) -> (20.0285, -21.907)
  spline S198 degree 2 poles (20.0285, -21.907) (20.0285, -21.3351) (19.9828, -21.1578) knots 0 0 0 1 1 1
  spline S199 degree 2 poles (19.9828, -21.1578) (19.9084, -20.8547) (19.348, -20.4029) (18.9191, -20.4029) knots 0 0 0 1 2 2 2
  spline S200 degree 2 poles (18.9191, -20.4029) (18.4044, -20.4029) (18.0841, -20.8033) knots 0 0 0 1 1 1
  spline S201 degree 2 poles (18.0841, -20.8033) (17.6666, -21.3294) (17.6666, -22.2845) knots 0 0 0 1 1 1
  spline S202 degree 2 poles (17.6666, -22.2845) (17.6666, -23.3711) (18.1413, -23.9544) knots 0 0 0 1 1 1
  spline S203 degree 2 poles (18.1413, -23.9544) (18.473, -24.3547) (18.9248, -24.3547) knots 0 0 0 1 1 1
  spline S204 degree 2 poles (18.9248, -24.3547) (19.1707, -24.3547) (19.4166, -24.2289) knots 0 0 0 1 1 1
  spline S205 degree 2 poles (19.4166, -24.2289) (19.5996, -24.1374) (20.0285, -23.6742) knots 0 0 0 1 1 1
  point P0 (45, 4)
  constraints: 2 other
extrude "押し出し7" cut sketch "スケッチ8" against normal blind 0.1
pattern_circular "円形状パターン1" count 2 over 360 about axis through (0, 0, -10) along (0, 0, 1) of "押し出し7"
equation "\"d21\" = d20"
